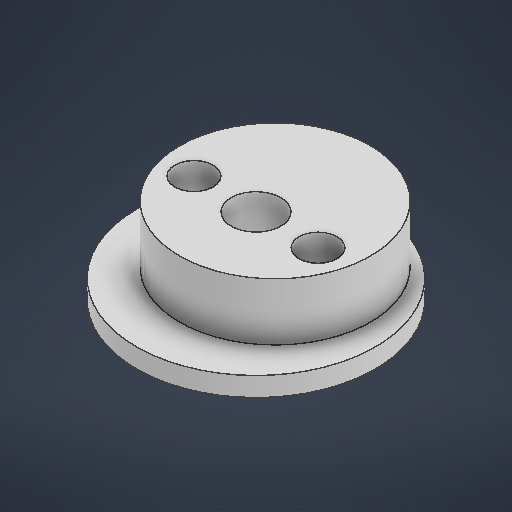
# Autodesk Inventor part: s2
Saved by Autodesk Inventor 2026.2 (Build 302298010, 298A)
## iProperties
Created: 2026-03-31
Part Number: s2
Material: 일반
Document SubType Name: Modeling
Designer: work
Density: 1 g/cm^3
Appearance: 기본값
Author: work
Autodesk Inventor part; units mm, degrees
ref_plane "YZ Plane" through (0, 0, 0) normal (1, 0, 0) x (0, 1, 0)
ref_plane "XZ Plane" through (0, 0, 0) normal (0, 1, 0) x (-1, 0, 0)
ref_plane "XY Plane" through (0, 0, 0) normal (0, 0, 1) x (1, 0, 0)
sketch "스케치1" plane through (0, 0, 0) normal (0, 1, 0) x (-1, 0, 0)
  line L0 (-6.5, 0) -> (6.5, 0)
  circle A0 centre (0, 0) radius 2.6
  circle A1 centre (6.5, 0) radius 2
  circle A2 centre (-6.5, 0) radius 2
  line L1 (0, 0) -> (0, -2) construction
  circle A3 centre (0, -2) radius 10
  circle A4 centre (0, 0) radius 12.5
  dimension "d0" = 13
  dimension "d1" = 5.2
  dimension "d2" = 4
  dimension "d3" = 4
  dimension "d4" = 2
  dimension "d5" = 20
  dimension "d6" = 25
  constraints: 5 centre point, 5 coincident, 4 end point, 1 horizontal, 1 midpoint, 1 vertical
  measures "d0" distance of L0.start L0.end
  measures "d1" diameter of A0
  measures "d2" diameter of A1
  measures "d3" diameter of A2
  measures "d4" distance of L1.start L1.end
  measures "d5" diameter of A3
  measures "d6" diameter of A4
extrude "돌출1" add sketch "스케치1" along normal blind 2 contours A4
extrude "돌출2" add sketch "스케치1" along normal blind 8 contours A3
